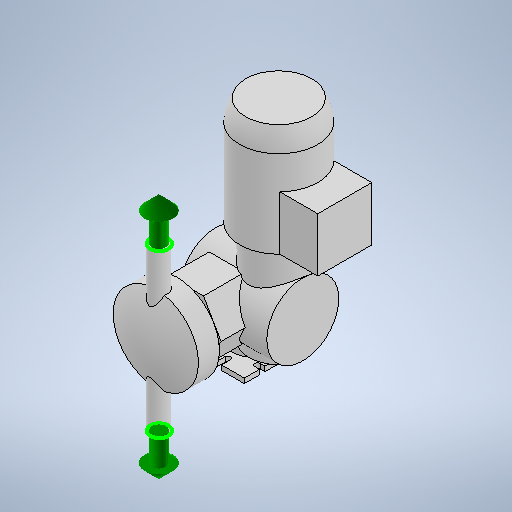
# Autodesk Inventor part: СДР 050 Дозатор реагента D1D108VPPC4000
Saved by Autodesk Inventor 2025 (Build 290162010, 162A)
## iProperties
Created: 2024-03-31
Part Number: СДР 050 Дозатор реагента D1D108VPPC4000
Material: Типовые
Document SubType Name: Modeling
Designer: pokla
Density: 1 g/cm^3
Appearance: По умолчанию
Stock Number: СДР 050 Дозатор реагента D1D108VPPC4000
Mass: 6323.73 g
Surface Area: 2975.53 cm^2
Volume: 6323.73 cm^3
allow_slope_adjustment: 0 ul
flow_configuration2: 1 ul
flow_direction: 2 ul
loss_method: 0 ul
radius: 15,000 mm
Author: pokla
Autodesk Inventor part; units mm, degrees
ref_plane "XZ Plane" through (0, 0, 0) normal (0, 1, 0) x (-1, 0, 0)
ref_plane "XY Plane" through (0, 0, 0) normal (0, 0, 1) x (1, 0, 0)
sketch "Эскиз1" plane through (0, 0, 0) normal (1, 0, 0) x (0, 1, 0)
  circle A0 centre (0, 0) radius 60
  dimension "d0" = 120
  constraints: 1 centre point, 1 coincident
  measures "d0" diameter of A0
extrude "Выдавливание1" add sketch "Эскиз1" along normal blind 95 and the other way blind 50
sketch "Эскиз2" plane through (0, 0, 0) normal (0, 0, 1) x (1, 0, 0)
  line L0 (29.4449, 51) -> (58.8897, 0)
  line L1 (58.8897, 0) -> (29.4449, -51)
  line L2 (29.4449, -51) -> (-29.4449, -51)
  line L3 (-29.4449, -51) -> (-58.8897, 0)
  line L4 (-58.8897, 0) -> (-29.4449, 51)
  line L5 (-29.4449, 51) -> (29.4449, 51)
  line L6 (-50, 60) -> (-50, -60) projected
  line L7 (-50, 60) -> (95, 60) projected
  point P0 (0, 0)
  point P1 (0, 0)
  point P2 (-50, 15.3975)
  point P3 (-50, -15.3975)
  dimension "d5" = 102
  dimension "d6" = 9
  constraints: 12 end point, 1 coincident, 1 horizontal alignment, 13 other
  measures "d5" distance between parallel lines of L2 L5
  measures "d6" distance between parallel lines of L7 L5
extrude "Выдавливание2" add sketch "Эскиз2" along normal blind 100 contours L0 L1 L2 L3 L6 L4 L5
sketch "Эскиз3" plane through (0, 0, 0) normal (0, 0, 1) x (1, 0, 0)
  line L0 (21.9393, 38) -> (43.8786, 0)
  line L1 (43.8786, 0) -> (21.9393, -38)
  line L2 (21.9393, -38) -> (-21.9393, -38)
  line L3 (-21.9393, -38) -> (-43.8786, 0)
  line L4 (-43.8786, 0) -> (-21.9393, 38)
  line L5 (-21.9393, 38) -> (21.9393, 38)
  line L6 (29.4449, 51) -> (-29.4449, 51) projected
  point P0 (0, 0)
  point P1 (0, 0)
  dimension "d9" = 13
  constraints: 12 end point, 1 coincident, 1 parallel, 13 other
  measures "d9" distance between parallel lines of L6 L5
extrude "Выдавливание3" add sketch "Эскиз3" along normal blind 115
sketch "Эскиз4" plane through (0, 0, 0) normal (0, 1, 0) x (-1, 0, 0)
  line L0 (-21.9393, 115) -> (21.9393, 115) projected
  line L1 (21.9393, 115) -> (-21.9393, 115) projected
  line L2 (0, 115) -> (0, 170)
  arc A0 (0, 170) -> (-71, 150) centre (0, 33.975) ccw
  line L3 (-71, 150) -> (-71, 115)
  line L4 (-71, 115) -> (0, 115)
  line L5 (-21.9393, 115) -> (-43.8786, 115) projected
  point P0 (0, 0)
  dimension "d12" = 55
  dimension "d13" = 35
  dimension "d14" = 142
  constraints: 6 end point, 2 point on circle, 1 centre point, 1 midpoint, 1 parallel, 1 perpendicular, 1 point on line, 1 vertical
  measures "d12" distance of L2.start L2.end
  measures "d13" distance of L3.start L3.end
  measures "d14" diameter of L3 L2
revolve "Вращение1" add sketch "Эскиз4" angle 360 about axis through (0, 0, 115) along (0, 0, 1)
sketch "Эскиз5" plane through (0, 0, 0) normal (0, 1, 0) x (-1, 0, 0)
  line L0 (71, 115) -> (-71, 115) projected
  circle A0 centre (0, 145) radius 15
  point P0 (0, 0)
  point P1 (0, 115)
  dimension "d16" = 30
  dimension "d17" = 30
  constraints: 1 centre point, 1 midpoint, 1 vertical alignment
  measures "d16" diameter of A0
  measures "d17" distance of point (0, 115) A0.centre
extrude "Выдавливание4" add sketch "Эскиз5" along normal mid plane 270
sketch "Эскиз6" plane through (0, 0, 0) normal (0, 1, 0) x (-1, 0, 0)
  line L0 (50, -60) -> (-95, -60) projected
  line L1 (-95, 60) -> (-95, -60) projected
  circle A0 centre (-45, -10) radius 50
  point P0 (0, 0)
  dimension "d20" = 100
  constraints: 2 tangent, 1 centre point
  measures "d20" diameter of A0
extrude "Выдавливание5" add sketch "Эскиз6" along normal mid plane 120 contours A0
ref_plane "РабПлоскость1" through (45, 0, 0) normal (1, 0, 0) x (0, 1, 0)
sketch "Эскиз7" plane through (45, 0, 0) normal (1, 0, 0) x (0, 1, 0)
  line L0 (44.7214, 40) -> (60, 40) construction
  line L1 (0, -60) -> (60, -60) construction
  line L2 (60, 0) -> (60, 40) projected
  line L3 (60, -60) -> (60, 0) projected
  line L4 (60, 40) -> (60, -60)
  line L5 (60, -10) -> (290, -10)
  line L6 (290, -10) -> (290, -65)
  arc A0 (255, -75) -> (290, -65) centre (255, -8.75) ccw
  line L7 (255, -75) -> (110, -75)
  line L8 (110, -75) -> (110, -60)
  line L9 (110, -60) -> (60, -60)
  point P0 (0, 0)
  dimension "d24" = 230
  dimension "d25" = 55
  dimension "d26" = 50
  dimension "d27" = 130
  dimension "d28" = 35
  constraints: 12 end point, 4 perpendicular, 2 point on circle, 1 centre point, 1 horizontal, 1 midpoint, 1 tangent
  measures "d24" distance of L5.start L5.end
  measures "d25" distance of L5.end L6.end
  measures "d26" distance of L8.end L1.end
  measures "d27" diameter of L7 L5
  measures "d28" distance from line of L7.start L6
revolve "Вращение2" add sketch "Эскиз7" angle 360 about axis through (45, 60, -10) along (0, 1, 0)
sketch "Эскиз10" plane through (45, 0, 0) normal (1, 0, 0) x (0, 1, 0)
  arc A0 (59.1608, -10) -> (-59.1608, -10) centre (0, 0) ccw projected
  arc A1 (-59.1608, -10) -> (59.1608, -10) centre (0, 0) ccw projected
  line L0 (-60, -60) -> (0, -60) projected
  line L1 (-60, 0) -> (-60, -60) projected
  line L2 (-60, -60) -> (-60, 0) projected
  line L3 (-60, -60) -> (0, -60) projected
  line L4 (-60, 0) -> (-60, -60)
  line L5 (-60, -60) -> (0, -60) projected
  constraints: 2 end point, 1 perpendicular, 1 other
extrude "Выдавливание8" cut sketch "Эскиз10" along normal through all both and the other way through all contours A0 A1 L0 L1
sketch "Эскиз8" plane through (0, 0, 0) normal (0, 0, 1) x (1, 0, 0)
  circle A0 centre (0, 10) radius 16
  line L0 (-50, 60) -> (-50, -60) projected
  point P0 (0, 0)
  point P1 (-50, 15.3975)
  point P2 (-50, -15.3975)
  point P3 (-50, 0)
  dimension "d30" = 32
  dimension "d31" = 50
  dimension "d32" = 10
  constraints: 1 centre point, 1 midpoint
  measures "d30" diameter of A0
  measures "d31" distance from line of L0 A0.centre
  measures "d32" vertical distance of point (-50, 0) A0.centre
extrude "Выдавливание6" add sketch "Эскиз8" against normal blind 120
sketch "Эскиз11" plane through (45, 0, 0) normal (1, 0, 0) x (0, 1, 0)
  line L0 (51, 37.5188) -> (51, 100) projected
  circle A0 centre (0, 0) radius 60 projected
  line L1 (110, 35) -> (200, 35)
  line L2 (200, 35) -> (200, -55)
  line L3 (200, -55) -> (110, -55)
  line L4 (110, -55) -> (110, 35)
  line L5 (110, 35) -> (200, -55) construction
  line L6 (200, 35) -> (110, -55) construction
  line L7 (290, -65) -> (290, 45) projected
  point P0 (59.1608, -10)
  point P1 (155, -10)
  point P2 (290, -10)
  dimension "d39" = 90
  dimension "d40" = 90
  constraints: 12 end point, 3 midpoint, 2 parallel, 2 perpendicular, 1 horizontal, 1 horizontal alignment, 1 other
  measures "d39" distance of L2.end L3.end
  measures "d40" distance between parallel lines of L2 L7
extrude "Выдавливание9" add sketch "Эскиз11" along normal blind 110 contours L1 L2 L3 L4
sketch "Эскиз13" plane through (-29.4449, -51, 100) normal (0, -1, 0) x (1, 0, 0)
  line L0 (45, -90) -> (45, -110) construction
  ellipse E0 centre (88.3346, -100) end of major axis (88.3346, -40) minor radius 34.641 (88.3346, -40) -> (61.6914, -61.6539) ccw projected
  line L1 (20, -90) -> (20, -110)
  line L2 (70, -110) -> (70, -90)
  arc A0 (70, -90) -> (20, -90) centre (45, -90) ccw
  arc A1 (20, -110) -> (70, -110) centre (45, -110) ccw
  line L3 (0, -68.393) -> (0, 0) projected
  line L4 (51.3842, 0) -> (7.5056, 0) projected
  point P0 (29.4449, -100)
  point P1 (45, -100)
  dimension "d43" = 50
  dimension "d44" = 20
  dimension "d45" = 20
  dimension "d46" = 100
  constraints: 8 end point, 4 point on circle, 4 tangent, 2 centre point, 1 midpoint, 1 parallel, 1 vertical, 1 other
  measures "d43" diameter of A1
  measures "d44" distance of L0.start L0.end
  measures "d45" distance between parallel lines of L1 L3
  measures "d46" distance from line of point (45, -100) L4
extrude "Выдавливание10" add sketch "Эскиз13" along normal blind 20
sketch "Эскиз14" plane through (-29.4449, -71, 100) normal (0, -1, 0) x (1, 0, 0)
  line L0 (89.4449, -162.5) -> (4.4449, -162.5)
  line L1 (4.4449, -162.5) -> (4.4449, -37.5)
  line L2 (4.4449, -37.5) -> (89.4449, -37.5)
  line L3 (89.4449, -37.5) -> (89.4449, -162.5)
  line L4 (89.4449, -162.5) -> (4.4449, -37.5) construction
  line L5 (4.4449, -162.5) -> (89.4449, -37.5) construction
  line L6 (70, -110) -> (70, -90) projected
  line L7 (-20.5551, -42.0093) -> (-20.5551, -160) projected
  point P0 (29.4449, -100)
  point P1 (46.9449, -100)
  point P2 (0, -68.393)
  point P3 (70, -100)
  dimension "d49" = 85
  dimension "d50" = 125
  dimension "d51" = 25
  constraints: 12 end point, 3 midpoint, 2 parallel, 1 horizontal, 1 horizontal alignment, 1 perpendicular
  measures "d49" distance of L1.end L2.end
  measures "d50" distance of L0.end L1.end
  measures "d51" distance between parallel lines of L1 L7
extrude "Выдавливание11" add sketch "Эскиз14" along normal blind 8
sketch "Эскиз15" plane through (-29.4449, -79, 100) normal (0, -1, 0) x (1, 0, 0)
  line L0 (89.4449, -37.5) -> (4.4449, -37.5) projected
  line L1 (4.4449, -37.5) -> (4.4449, -162.5) projected
  line L2 (4.4449, -162.5) -> (89.4449, -162.5) projected
  line L3 (89.4449, -162.5) -> (89.4449, -37.5) projected
  circle A0 centre (46.9449, -52.5) radius 4.5
  circle A1 centre (81.4449, -67.5) radius 4.5
  circle A2 centre (12.4449, -67.5) radius 4.5
  circle A3 centre (81.4449, -132.5) radius 4.5
  circle A4 centre (12.4449, -132.5) radius 4.5
  circle A5 centre (46.9449, -147.5) radius 4.5
  line L4 (46.9449, -37.5) -> (46.9449, -162.5) construction
  line L5 (89.4449, -100) -> (4.4449, -100) construction
  line L6 (42.4449, -52.5) -> (42.4449, -37.5)
  line L7 (51.4449, -52.5) -> (51.4449, -37.5)
  line L8 (81.4449, -63) -> (89.4449, -63)
  line L9 (81.4449, -72) -> (89.4449, -72)
  line L10 (12.4449, -63) -> (4.4449, -63)
  line L11 (12.4449, -72) -> (4.4449, -72)
  line L12 (81.4449, -128) -> (89.4449, -128)
  line L13 (81.4449, -137) -> (89.4449, -137)
  line L14 (42.4449, -147.5) -> (42.4449, -162.5)
  line L15 (51.4449, -147.5) -> (51.4449, -162.5)
  line L16 (12.4449, -128) -> (4.4449, -128)
  line L17 (12.4449, -137) -> (4.4449, -137)
  point P0 (29.4449, -100)
  point P1 (46.9449, -100)
  dimension "d54" = 9
  dimension "d55" = 65
  dimension "d57" = 69
  dimension "d58" = 95
  constraints: 28 end point, 12 perpendicular, 12 point on circle, 12 point on line, 12 tangent, 6 centre point, 5 midpoint, 2 vertical alignment, 1 equal radius, 4 other
  measures "d54" diameter of A0
  measures "d55" distance of A3.centre A1.centre
  measures "d57" distance of A2.centre A1.centre
  measures "d58" distance of A5.centre A0.centre
extrude "Выдавливание12" cut sketch "Эскиз15" against normal blind 8 contours L7 A0 L6 L0 | L3 L9 A1 L8 | A0 | A1 | L3 L13 A3 L12 | L10 A2 L11 L1 | A3 | A2 | L16 A4 L17 L1 | L2 L14 A5 L15 | A4 | A5
